Autodesk Fusion 360 part; units mm, degrees
(part 2 of 2)
extrude "Bottom cover snap 55" add sketch "Bottom cover snap 55 outline" along normal blind 5 bodies 21 in component "02 Snap-on front cover - PRINT"
ref_plane "WorkPlane21" through (52.5, 0, 0) normal (1, 0, 0) x (0, 1, 0) in component "02 Snap-on front cover - PRINT"
sketch "Top cover snap 55 outline" plane through (52.5, 0, 0) normal (1, 0, 0) x (0, 0, -1) in component "02 Snap-on front cover - PRINT"
  line L0 (-163.45, -14.2) -> (-164.25, -14.2)
  line L1 (-164.25, -14.2) -> (-164.25, -9)
  line L2 (-164.25, -9) -> (-165.2, -9)
  line L3 (-165.2, -9) -> (-165.2, -8.2)
  line L4 (-165.2, -8.2) -> (-164.25, -6.8)
  line L5 (-164.25, -6.8) -> (-163.45, -6.8)
  line L6 (-163.45, -6.8) -> (-163.45, -14.2)
extrude "Top cover snap 55" add sketch "Top cover snap 55 outline" along normal blind 5 bodies 21 in component "02 Snap-on front cover - PRINT"
ref_plane "WorkPlane22" through (156.5, 0, 0) normal (1, 0, 0) x (0, 1, 0) in component "02 Snap-on front cover - PRINT"
sketch "Bottom cover snap 159 outline" plane through (156.5, 0, 0) normal (1, 0, 0) x (0, 0, -1) in component "02 Snap-on front cover - PRINT"
  line L0 (-71.75, -14.2) -> (-72.95, -14.2)
  line L1 (-72.95, -14.2) -> (-72.95, -1.8)
  line L2 (-72.95, -1.8) -> (-71.75, -1.8)
  line L3 (-71.75, -1.8) -> (-70.8, -3.2)
  line L4 (-70.8, -3.2) -> (-70.8, -4)
  line L5 (-70.8, -4) -> (-71.75, -4)
  line L6 (-71.75, -4) -> (-71.75, -14.2)
extrude "Bottom cover snap 159" add sketch "Bottom cover snap 159 outline" along normal blind 5 bodies 21 in component "02 Snap-on front cover - PRINT"
ref_plane "WorkPlane23" through (156.5, 0, 0) normal (1, 0, 0) x (0, 1, 0) in component "02 Snap-on front cover - PRINT"
sketch "Top cover snap 159 outline" plane through (156.5, 0, 0) normal (1, 0, 0) x (0, 0, -1) in component "02 Snap-on front cover - PRINT"
  line L0 (-163.45, -14.2) -> (-164.25, -14.2)
  line L1 (-164.25, -14.2) -> (-164.25, -9)
  line L2 (-164.25, -9) -> (-165.2, -9)
  line L3 (-165.2, -9) -> (-165.2, -8.2)
  line L4 (-165.2, -8.2) -> (-164.25, -6.8)
  line L5 (-164.25, -6.8) -> (-163.45, -6.8)
  line L6 (-163.45, -6.8) -> (-163.45, -14.2)
extrude "Top cover snap 159" add sketch "Top cover snap 159 outline" along normal blind 5 bodies 21 in component "02 Snap-on front cover - PRINT"
ref_plane "WorkPlane24" through (0, 0, 72.3) normal (0, 0, 1) x (1, 0, 0) in component "02 Snap-on front cover - PRINT"
sketch "Ribbon roof attachment outline" plane through (0, 0, 72.3) normal (0, 0, 1) x (1, 0, 0) in component "02 Snap-on front cover - PRINT"
  line L0 (96, -16.2) -> (118, -16.2)
  line L1 (118, -16.2) -> (118, -12.6)
  line L2 (118, -12.6) -> (96, -12.6)
  line L3 (96, -12.6) -> (96, -16.2)
extrude "Ribbon roof attachment" add sketch "Ribbon roof attachment outline" along normal blind 2 bodies 21 in component "02 Snap-on front cover - PRINT"
ref_plane "WorkPlane25" through (0, 0, -4) normal (0, 0, 1) x (1, 0, 0) in component "02 Snap-on front cover - PRINT"
sketch "Continuous ribbon roof outline" plane through (0, 0, -4) normal (0, 0, 1) x (1, 0, 0) in component "02 Snap-on front cover - PRINT"
  line L0 (96, -13.8) -> (118, -13.8)
  line L1 (118, -13.8) -> (118, -12.6)
  line L2 (118, -12.6) -> (96, -12.6)
  line L3 (96, -12.6) -> (96, -13.8)
extrude "Continuous ribbon roof" add sketch "Continuous ribbon roof outline" along normal blind 78.3 bodies 21 in component "02 Snap-on front cover - PRINT"
ref_plane "WorkPlane26" through (0, 0, -4) normal (0, 0, 1) x (1, 0, 0) in component "02 Snap-on front cover - PRINT"
sketch "Ribbon roof side flange 96 outline" plane through (0, 0, -4) normal (0, 0, 1) x (1, 0, 0) in component "02 Snap-on front cover - PRINT"
  line L0 (96, -12.6) -> (98, -12.6)
  line L1 (98, -12.6) -> (98, -11.2)
  line L2 (98, -11.2) -> (96, -11.2)
  line L3 (96, -11.2) -> (96, -12.6)
extrude "Ribbon roof side flange 96" add sketch "Ribbon roof side flange 96 outline" along normal blind 76.3 bodies 21 in component "02 Snap-on front cover - PRINT"
ref_plane "WorkPlane27" through (0, 0, -4) normal (0, 0, 1) x (1, 0, 0) in component "02 Snap-on front cover - PRINT"
sketch "Ribbon roof side flange 116 outline" plane through (0, 0, -4) normal (0, 0, 1) x (1, 0, 0) in component "02 Snap-on front cover - PRINT"
  line L0 (116, -12.6) -> (118, -12.6)
  line L1 (118, -12.6) -> (118, -11.2)
  line L2 (118, -11.2) -> (116, -11.2)
  line L3 (116, -11.2) -> (116, -12.6)
extrude "Ribbon roof side flange 116" add sketch "Ribbon roof side flange 116 outline" along normal blind 76.3 bodies 21 in component "02 Snap-on front cover - PRINT"
ref_plane "WorkPlane28" through (0, 0, 1) normal (0, 0, 1) x (1, 0, 0) in component "02 Snap-on front cover - PRINT"
sketch "Lower ribbon cover catch bridge outline" plane through (0, 0, 1) normal (0, 0, 1) x (1, 0, 0) in component "02 Snap-on front cover - PRINT"
  line L0 (84.4, -13.8) -> (129.6, -13.8)
  line L1 (129.6, -13.8) -> (129.6, -12.6)
  line L2 (129.6, -12.6) -> (84.4, -12.6)
  line L3 (84.4, -12.6) -> (84.4, -13.8)
extrude "Lower ribbon cover catch bridge" add sketch "Lower ribbon cover catch bridge outline" along normal blind 6 bodies 21 in component "02 Snap-on front cover - PRINT"
ref_plane "WorkPlane29" through (0, 0, 1.5) normal (0, 0, 1) x (1, 0, 0) in component "02 Snap-on front cover - PRINT"
sketch "Left ribbon cover release catch outline" plane through (0, 0, 1.5) normal (0, 0, 1) x (1, 0, 0) in component "02 Snap-on front cover - PRINT"
  line L0 (84.4, -13.8) -> (85.6, -13.8)
  line L1 (85.6, -13.8) -> (85.6, -5.8)
  line L2 (85.6, -5.8) -> (86.6, -5.8)
  line L3 (86.6, -5.8) -> (86.6, -5.2)
  line L4 (86.6, -5.2) -> (85.6, -4.8)
  line L5 (85.6, -4.8) -> (84.4, -4.8)
  line L6 (84.4, -4.8) -> (84.4, -13.8)
extrude "Left ribbon cover release catch" add sketch "Left ribbon cover release catch outline" along normal blind 5 bodies 21 in component "02 Snap-on front cover - PRINT"
ref_plane "WorkPlane30" through (0, 0, 1.5) normal (0, 0, 1) x (1, 0, 0) in component "02 Snap-on front cover - PRINT"
sketch "Right ribbon cover release catch outline" plane through (0, 0, 1.5) normal (0, 0, 1) x (1, 0, 0) in component "02 Snap-on front cover - PRINT"
  line L0 (129.6, -13.8) -> (128.4, -13.8)
  line L1 (128.4, -13.8) -> (128.4, -5.8)
  line L2 (128.4, -5.8) -> (127.4, -5.8)
  line L3 (127.4, -5.8) -> (127.4, -5.2)
  line L4 (127.4, -5.2) -> (128.4, -4.8)
  line L5 (128.4, -4.8) -> (129.6, -4.8)
  line L6 (129.6, -4.8) -> (129.6, -13.8)
extrude "Right ribbon cover release catch" add sketch "Right ribbon cover release catch outline" along normal blind 5 bodies 21 in component "02 Snap-on front cover - PRINT"
ref_plane "WorkPlane1" through (0, 0, -29) normal (0, 0, 1) x (1, 0, 0) in component "03 Snap-on downward camera guard - PRINT"
sketch "Camera guard shell outline" plane through (0, 0, -29) normal (0, 0, 1) x (1, 0, 0) in component "03 Snap-on downward camera guard - PRINT"
  line L0 (85.2, -26.45) -> (128.8, -26.45)
  line L1 (130.8, -24.45) -> (130.8, 19.15)
  line L2 (128.8, 21.15) -> (85.2, 21.15)
  line L3 (83.2, 19.15) -> (83.2, -24.45)
  arc A0 (128.8, -26.45) -> (130.8, -24.45) centre (128.8, -24.45) ccw
  arc A1 (130.8, 19.15) -> (128.8, 21.15) centre (128.8, 19.15) ccw
  arc A2 (85.2, 21.15) -> (83.2, 19.15) centre (85.2, 19.15) ccw
  arc A3 (83.2, -24.45) -> (85.2, -26.45) centre (85.2, -24.45) ccw
extrude "Camera guard shell" add sketch "Camera guard shell outline" along normal blind 18.6 separate body makes body 22 in component "03 Snap-on downward camera guard - PRINT"
ref_plane "WorkPlane2" through (0, 0, -26.6) normal (0, 0, 1) x (1, 0, 0) in component "03 Snap-on downward camera guard - PRINT"
sketch "Camera cavity outline" plane through (0, 0, -26.6) normal (0, 0, 1) x (1, 0, 0) in component "03 Snap-on downward camera guard - PRINT"
  line L0 (85.6, -24.05) -> (128.4, -24.05)
  line L1 (128.4, -24.05) -> (128.4, 18.75)
  line L2 (128.4, 18.75) -> (85.6, 18.75)
  line L3 (85.6, 18.75) -> (85.6, -24.05)
extrude "Camera cavity" cut sketch "Camera cavity outline" along normal blind 16.3 bodies 22 in component "03 Snap-on downward camera guard - PRINT"
ref_plane "WorkPlane3" through (0, 0, -29.1) normal (0, 0, 1) x (1, 0, 0) in component "03 Snap-on downward camera guard - PRINT"
sketch "Fisheye aperture layout" plane through (0, 0, -29.1) normal (0, 0, 1) x (1, 0, 0) in component "03 Snap-on downward camera guard - PRINT"
  circle A0 centre (107, 0) radius 11
extrude "Fisheye aperture" cut sketch "Fisheye aperture layout" along normal blind 2.6 bodies 22 in component "03 Snap-on downward camera guard - PRINT"
ref_plane "WorkPlane4" through (0, 0, -19) normal (0, 0, 1) x (1, 0, 0) in component "03 Snap-on downward camera guard - PRINT"
sketch "Ribbon exit outline" plane through (0, 0, -19) normal (0, 0, 1) x (1, 0, 0) in component "03 Snap-on downward camera guard - PRINT"
  line L0 (98, -26.6) -> (116, -26.6)
  line L1 (116, -26.6) -> (116, -23.9)
  line L2 (116, -23.9) -> (98, -23.9)
  line L3 (98, -23.9) -> (98, -26.6)
extrude "Ribbon exit" cut sketch "Ribbon exit outline" along normal blind 8.7 bodies 22 in component "03 Snap-on downward camera guard - PRINT"
ref_plane "WorkPlane5" through (0, 0, -25) normal (0, 0, 1) x (1, 0, 0) in component "03 Snap-on downward camera guard - PRINT"
sketch "L flexible tongue clearance outline" plane through (0, 0, -25) normal (0, 0, 1) x (1, 0, 0) in component "03 Snap-on downward camera guard - PRINT"
  line L0 (83.1, -3.6) -> (85.7, -3.6)
  line L1 (85.7, -3.6) -> (85.7, 3.6)
  line L2 (85.7, 3.6) -> (83.1, 3.6)
  line L3 (83.1, 3.6) -> (83.1, -3.6)
extrude "L flexible tongue clearance" cut sketch "L flexible tongue clearance outline" along normal blind 14.7 bodies 22 in component "03 Snap-on downward camera guard - PRINT"
ref_plane "WorkPlane6" through (0, 0, -25) normal (0, 0, 1) x (1, 0, 0) in component "03 Snap-on downward camera guard - PRINT"
sketch "R flexible tongue clearance outline" plane through (0, 0, -25) normal (0, 0, 1) x (1, 0, 0) in component "03 Snap-on downward camera guard - PRINT"
  line L0 (128.3, -3.6) -> (130.9, -3.6)
  line L1 (130.9, -3.6) -> (130.9, 3.6)
  line L2 (130.9, 3.6) -> (128.3, 3.6)
  line L3 (128.3, 3.6) -> (128.3, -3.6)
extrude "R flexible tongue clearance" cut sketch "R flexible tongue clearance outline" along normal blind 14.7 bodies 22 in component "03 Snap-on downward camera guard - PRINT"
ref_plane "WorkPlane7" through (0, -3, 0) normal (0, 1, 0) x (0, 0, 1) in component "03 Snap-on downward camera guard - PRINT"
sketch "Left releasable camera snap outline" plane through (0, -3, 0) normal (0, 1, 0) x (1, 0, 0) in component "03 Snap-on downward camera guard - PRINT"
  line L0 (84.4, 25) -> (85.6, 25)
  line L1 (85.6, 25) -> (85.6, 8.5)
  line L2 (85.6, 8.5) -> (86.7, 8.5)
  line L3 (86.7, 8.5) -> (86.7, 7)
  line L4 (86.7, 7) -> (85.6, 5.4)
  line L5 (85.6, 5.4) -> (84.4, 5.4)
  line L6 (84.4, 5.4) -> (84.4, 25)
extrude "Left releasable camera snap" add sketch "Left releasable camera snap outline" along normal blind 6 bodies 22 in component "03 Snap-on downward camera guard - PRINT"
ref_plane "WorkPlane8" through (0, -3, 0) normal (0, 1, 0) x (0, 0, 1) in component "03 Snap-on downward camera guard - PRINT"
sketch "Right releasable camera snap outline" plane through (0, -3, 0) normal (0, 1, 0) x (1, 0, 0) in component "03 Snap-on downward camera guard - PRINT"
  line L0 (129.6, 25) -> (128.4, 25)
  line L1 (128.4, 25) -> (128.4, 8.5)
  line L2 (128.4, 8.5) -> (127.3, 8.5)
  line L3 (127.3, 8.5) -> (127.3, 7)
  line L4 (127.3, 7) -> (128.4, 5.4)
  line L5 (128.4, 5.4) -> (129.6, 5.4)
  line L6 (129.6, 5.4) -> (129.6, 25)
extrude "Right releasable camera snap" add sketch "Right releasable camera snap outline" along normal blind 6 bodies 22 in component "03 Snap-on downward camera guard - PRINT"
ref_plane "WorkPlane1" through (99, 0, 0) normal (1, 0, 0) x (0, 1, 0) in component "REFERENCE - nominal ribbon clearance 16 x 0.35 mm"
sketch "Nominal ribbon route outline" plane through (99, 0, 0) normal (1, 0, 0) x (0, 0, -1) in component "REFERENCE - nominal ribbon clearance 16 x 0.35 mm"
  line L0 (13, -17.675) -> (8.9063, -17.675)
  line L1 (8.9063, -17.675) -> (6.825, -14.553)
  line L2 (6.825, -14.553) -> (6.825, -13.0967)
  line L3 (6.825, -13.0967) -> (3.4496, -10.975)
  line L4 (3.4496, -10.975) -> (-73, -10.975)
  line L5 (-73, -10.975) -> (-73, -10.625)
  line L6 (-73, -10.625) -> (3.5504, -10.625)
  line L7 (3.5504, -10.625) -> (7.175, -12.9033)
  line L8 (7.175, -12.9033) -> (7.175, -14.447)
  line L9 (7.175, -14.447) -> (9.0937, -17.325)
  line L10 (9.0937, -17.325) -> (13, -17.325)
  line L11 (13, -17.325) -> (13, -17.675)
extrude "Nominal ribbon route" add sketch "Nominal ribbon route outline" along normal blind 16 separate body makes body 23 in component "REFERENCE - nominal ribbon clearance 16 x 0.35 mm"
ref_plane "WorkPlane31" through (0, -16.2, 0) normal (0, 1, 0) x (0, 0, 1) in component "02 Snap-on front cover - PRINT"
sketch "Purdue Hackers official flat logo recess 1 outline" plane through (0, -16.2, 0) normal (0, 1, 0) x (1, 0, 0) in component "02 Snap-on front cover - PRINT"
  line L0 (101.6666, -76) -> (91, -76)
  line L1 (91, -76) -> (91, -86.2945)
  line L2 (91, -86.2945) -> (101.6666, -86.2945)
  line L3 (101.6666, -86.2945) -> (101.6666, -76)
  line L4 (101.6666, -76) -> (101.6666, -76)
extrude "Purdue Hackers official flat logo recess 1" cut sketch "Purdue Hackers official flat logo recess 1 outline" along normal blind 0.6 bodies 21 in component "02 Snap-on front cover - PRINT"
ref_plane "WorkPlane32" through (0, -16.2, 0) normal (0, 1, 0) x (0, 0, 1) in component "02 Snap-on front cover - PRINT"
sketch "Purdue Hackers official flat logo recess 2 outline" plane through (0, -16.2, 0) normal (0, 1, 0) x (1, 0, 0) in component "02 Snap-on front cover - PRINT"
  line L0 (112.3334, -96.5892) -> (123, -96.5892)
  line L1 (123, -96.5892) -> (123, -76)
  line L2 (123, -76) -> (112.3334, -76)
  line L3 (112.3334, -76) -> (112.3334, -86.2945)
  line L4 (112.3334, -86.2945) -> (101.6666, -86.2945)
  line L5 (101.6666, -86.2945) -> (101.6666, -106.8837)
  line L6 (101.6666, -106.8837) -> (112.3334, -106.8837)
  line L7 (112.3334, -106.8837) -> (112.3334, -96.5892)
  line L8 (112.3334, -96.5892) -> (112.3334, -96.5892)
extrude "Purdue Hackers official flat logo recess 2" cut sketch "Purdue Hackers official flat logo recess 2 outline" along normal blind 0.6 bodies 21 in component "02 Snap-on front cover - PRINT"
ref_plane "WorkPlane33" through (0, -16.2, 0) normal (0, 1, 0) x (0, 0, 1) in component "02 Snap-on front cover - PRINT"
sketch "Logo corner separation for manifold print outline" plane through (0, -16.2, 0) normal (0, 1, 0) x (1, 0, 0) in component "02 Snap-on front cover - PRINT"
  line L0 (101.6666, -86.2945) -> (101.2666, -86.2945)
  line L1 (101.2666, -86.2945) -> (101.6666, -85.8945)
  line L2 (101.6666, -85.8945) -> (101.6666, -86.2945)
extrude "Logo corner separation for manifold print" add sketch "Logo corner separation for manifold print outline" along normal blind 0.6 bodies 21 in component "02 Snap-on front cover - PRINT"
ref_plane "WorkPlane36" through (0, 0, -9) normal (0, 0, 1) x (1, 0, 0) in component "01 Integral case mount and camera holder - PRINT"
sketch "7 mm retaining hook thickness 25 outline" plane through (0, 0, -9) normal (0, 0, 1) x (1, 0, 0) in component "01 Integral case mount and camera holder - PRINT"
  line L0 (12, -11) -> (38, -11)
  line L1 (38, -11) -> (38, 45)
  line L2 (38, 45) -> (12, 45)
  line L3 (12, 45) -> (12, -11)
extrude "7 mm retaining hook thickness 25" add sketch "7 mm retaining hook thickness 25 outline" along normal blind 2 bodies 20 in component "01 Integral case mount and camera holder - PRINT"
ref_plane "WorkPlane37" through (0, 0, -9) normal (0, 0, 1) x (1, 0, 0) in component "01 Integral case mount and camera holder - PRINT"
sketch "7 mm retaining hook thickness 189 outline" plane through (0, 0, -9) normal (0, 0, 1) x (1, 0, 0) in component "01 Integral case mount and camera holder - PRINT"
  line L0 (176, -11) -> (202, -11)
  line L1 (202, -11) -> (202, 45)
  line L2 (202, 45) -> (176, 45)
  line L3 (176, 45) -> (176, -11)
extrude "7 mm retaining hook thickness 189" add sketch "7 mm retaining hook thickness 189 outline" along normal blind 2 bodies 20 in component "01 Integral case mount and camera holder - PRINT"
fillet "Rounded retaining arm upper roots" radius 1.5 4 edges at (189, -11, 65) (25, -11, 65) (189, -6, 65) (25, -6, 65) on bodies 20 in component "01 Integral case mount and camera holder - PRINT"
fillet "Rounded retaining arm inner knees" radius 1.5 4 edges at (25, -6, 7) (189, -6, 7) (189, -1, -2) (25, -1, -2) on bodies 20 in component "01 Integral case mount and camera holder - PRINT"
fillet "Rounded retaining arm outside heels" radius 2 2 edges at (25, -11, -9) (189, -11, -9) on bodies 20 in component "01 Integral case mount and camera holder - PRINT"
fillet "Lower service cover clip root relief" radius 0.6 4 edges at (159, -14.2, 71.75) (55, -14.2, 71.75) (159, -14.2, 72.95) (55, -14.2, 72.95) on bodies 21 in component "02 Snap-on front cover - PRINT"
fillet "Upper service cover clip root relief" radius 0.4 4 edges at (159, -14.2, 163.45) (55, -14.2, 163.45) (159, -14.2, 164.25) (55, -14.2, 164.25) on bodies 21 in component "02 Snap-on front cover - PRINT"
ref_plane "WorkPlane38" through (0, 15.6, 0) normal (0, 1, 0) x (0, 0, 1) in component "01 Integral case mount and camera holder - PRINT"
sketch "Pi screw entry relief - 0.2 mm deep layout" plane through (0, 15.6, 0) normal (0, 1, 0) x (1, 0, 0) in component "01 Integral case mount and camera holder - PRINT"
  circle A0 centre (149.5, -78.5) radius 1.4
  circle A1 centre (198.5, -78.5) radius 1.4
  circle A2 centre (149.5, -136.5) radius 1.4
  circle A3 centre (198.5, -136.5) radius 1.4
extrude "Pi screw entry relief - 0.2 mm deep" cut sketch "Pi screw entry relief - 0.2 mm deep layout" along normal blind 0.2 bodies 20 in component "01 Integral case mount and camera holder - PRINT"
ref_plane "WorkPlane39" through (0, 0, -13.5) normal (0, 0, 1) x (1, 0, 0) in component "01 Integral case mount and camera holder - PRINT"
sketch "Camera screw entry relief - 0.2 mm deep layout" plane through (0, 0, -13.5) normal (0, 0, 1) x (1, 0, 0) in component "01 Integral case mount and camera holder - PRINT"
  circle A0 centre (117.5, -7.15) radius 1.1
  circle A1 centre (117.5, 6.35) radius 1.1
  circle A2 centre (96.5, -7.15) radius 1.1
  circle A3 centre (96.5, 6.35) radius 1.1
extrude "Camera screw entry relief - 0.2 mm deep" cut sketch "Camera screw entry relief - 0.2 mm deep layout" along normal blind 0.2 bodies 20 in component "01 Integral case mount and camera holder - PRINT"
sketch "Screw-fit coupon base outline" plane through (0, 0, 0) normal (0, 0, 1) x (1, 0, 0) in component "08 Screw-fit test coupon - TEST PRINT"
  line L0 (245, 0) -> (297, 0)
  line L1 (297, 0) -> (297, 44)
  line L2 (297, 44) -> (245, 44)
  line L3 (245, 44) -> (245, 0)
extrude "Screw-fit coupon base" add sketch "Screw-fit coupon base outline" along normal blind 2 separate body makes body 24 in component "08 Screw-fit test coupon - TEST PRINT"
ref_plane "WorkPlane1" through (0, 0, 2) normal (0, 0, 1) x (1, 0, 0) in component "08 Screw-fit test coupon - TEST PRINT"
sketch "Coupon label M2" plane through (0, 0, 2) normal (0, 0, 1) x (1, 0, 0) in component "08 Screw-fit test coupon - TEST PRINT"
  line L0 (246, 0.2) -> (246.5, 0.2)
  line L1 (246.5, 0.2) -> (246.5, 5.2)
  line L2 (246.5, 5.2) -> (246, 5.2)
  line L3 (246, 5.2) -> (246, 0.2)
  line L4 (249.5, 0.2) -> (250, 0.2)
  line L5 (250, 0.2) -> (250, 5.2)
  line L6 (250, 5.2) -> (249.5, 5.2)
  line L7 (249.5, 5.2) -> (249.5, 0.2)
  line L8 (246.65, 5.2) -> (247.9, 3.4)
  line L9 (247.9, 3.4) -> (247.55, 2.9)
  line L10 (247.55, 2.9) -> (246.65, 4.2)
  line L11 (246.65, 4.2) -> (246.65, 5.2)
  line L12 (249.35, 5.2) -> (248.1, 3.4)
  line L13 (248.1, 3.4) -> (248.45, 2.9)
  line L14 (248.45, 2.9) -> (249.35, 4.2)
  line L15 (249.35, 4.2) -> (249.35, 5.2)
  line L16 (251.65, 4.7) -> (253.35, 4.7)
  line L17 (253.35, 4.7) -> (253.35, 5.2)
  line L18 (253.35, 5.2) -> (251.65, 5.2)
  line L19 (251.65, 5.2) -> (251.65, 4.7)
  line L20 (253.5, 3.1) -> (254, 3.1)
  line L21 (254, 3.1) -> (254, 4.55)
  line L22 (254, 4.55) -> (253.5, 4.55)
  line L23 (253.5, 4.55) -> (253.5, 3.1)
  line L24 (251.65, 0.2) -> (253.35, 0.2)
  line L25 (253.35, 0.2) -> (253.35, 0.7)
  line L26 (253.35, 0.7) -> (251.65, 0.7)
  line L27 (251.65, 0.7) -> (251.65, 0.2)
  line L28 (251, 0.85) -> (251.5, 0.85)
  line L29 (251.5, 0.85) -> (251.5, 2.3)
  line L30 (251.5, 2.3) -> (251, 2.3)
  line L31 (251, 2.3) -> (251, 0.85)
  line L32 (251.65, 2.45) -> (253.35, 2.45)
  line L33 (253.35, 2.45) -> (253.35, 2.95)
  line L34 (253.35, 2.95) -> (251.65, 2.95)
  line L35 (251.65, 2.95) -> (251.65, 2.45)
extrude "Raised coupon label M2" add sketch "Coupon label M2" along normal blind 0.4 bodies 24 in component "08 Screw-fit test coupon - TEST PRINT"
ref_plane "WorkPlane2" through (0, 0, 2) normal (0, 0, 1) x (1, 0, 0) in component "08 Screw-fit test coupon - TEST PRINT"
sketch "M2 pilot 1.6 boss layout" plane through (0, 0, 2) normal (0, 0, 1) x (1, 0, 0) in component "08 Screw-fit test coupon - TEST PRINT"
  circle A0 centre (253, 9) radius 3.2
extrude "M2 pilot 1.6 boss" add sketch "M2 pilot 1.6 boss layout" along normal blind 7 bodies 24 in component "08 Screw-fit test coupon - TEST PRINT"
ref_plane "WorkPlane3" through (0, 0, 9) normal (0, 0, 1) x (1, 0, 0) in component "08 Screw-fit test coupon - TEST PRINT"
sketch "M2 pilot 1.6 bore layout" plane through (0, 0, 9) normal (0, 0, 1) x (1, 0, 0) in component "08 Screw-fit test coupon - TEST PRINT"
  circle A0 centre (253, 9) radius 0.8
extrude "M2 pilot 1.6 bore" cut sketch "M2 pilot 1.6 bore layout" against normal blind 5.2 bodies 24 in component "08 Screw-fit test coupon - TEST PRINT"
ref_plane "WorkPlane4" through (0, 0, 9) normal (0, 0, 1) x (1, 0, 0) in component "08 Screw-fit test coupon - TEST PRINT"
sketch "M2 pilot 1.6 board clearance layout" plane through (0, 0, 9) normal (0, 0, 1) x (1, 0, 0) in component "08 Screw-fit test coupon - TEST PRINT"
  circle A0 centre (253, 9) radius 1.1
extrude "M2 pilot 1.6 board clearance" cut sketch "M2 pilot 1.6 board clearance layout" against normal blind 1.4 bodies 24 in component "08 Screw-fit test coupon - TEST PRINT"
ref_plane "WorkPlane5" through (0, 0, 2) normal (0, 0, 1) x (1, 0, 0) in component "08 Screw-fit test coupon - TEST PRINT"
sketch "Coupon label 1.6" plane through (0, 0, 2) normal (0, 0, 1) x (1, 0, 0) in component "08 Screw-fit test coupon - TEST PRINT"
  line L0 (250.5, 16.9) -> (251, 16.9)
  line L1 (251, 16.9) -> (251, 18.35)
  line L2 (251, 18.35) -> (250.5, 18.35)
  line L3 (250.5, 18.35) -> (250.5, 16.9)
  line L4 (250.5, 14.65) -> (251, 14.65)
  line L5 (251, 14.65) -> (251, 16.1)
  line L6 (251, 16.1) -> (250.5, 16.1)
  line L7 (250.5, 16.1) -> (250.5, 14.65)
  circle A0 centre (252.3, 14.3) radius 0.3
  line L8 (254.05, 18.5) -> (255.75, 18.5)
  line L9 (255.75, 18.5) -> (255.75, 19)
  line L10 (255.75, 19) -> (254.05, 19)
  line L11 (254.05, 19) -> (254.05, 18.5)
  line L12 (255.9, 14.65) -> (256.4, 14.65)
  line L13 (256.4, 14.65) -> (256.4, 16.1)
  line L14 (256.4, 16.1) -> (255.9, 16.1)
  line L15 (255.9, 16.1) -> (255.9, 14.65)
  line L16 (254.05, 14) -> (255.75, 14)
  line L17 (255.75, 14) -> (255.75, 14.5)
  line L18 (255.75, 14.5) -> (254.05, 14.5)
  line L19 (254.05, 14.5) -> (254.05, 14)
  line L20 (253.4, 14.65) -> (253.9, 14.65)
  line L21 (253.9, 14.65) -> (253.9, 16.1)
  line L22 (253.9, 16.1) -> (253.4, 16.1)
  line L23 (253.4, 16.1) -> (253.4, 14.65)
  line L24 (253.4, 16.9) -> (253.9, 16.9)
  line L25 (253.9, 16.9) -> (253.9, 18.35)
  line L26 (253.9, 18.35) -> (253.4, 18.35)
  line L27 (253.4, 18.35) -> (253.4, 16.9)
  line L28 (254.05, 16.25) -> (255.75, 16.25)
  line L29 (255.75, 16.25) -> (255.75, 16.75)
  line L30 (255.75, 16.75) -> (254.05, 16.75)
  line L31 (254.05, 16.75) -> (254.05, 16.25)
extrude "Raised coupon label 1.6" add sketch "Coupon label 1.6" along normal blind 0.4 bodies 24 in component "08 Screw-fit test coupon - TEST PRINT"
ref_plane "WorkPlane6" through (0, 0, 2) normal (0, 0, 1) x (1, 0, 0) in component "08 Screw-fit test coupon - TEST PRINT"
sketch "M2 pilot 1.7 boss layout" plane through (0, 0, 2) normal (0, 0, 1) x (1, 0, 0) in component "08 Screw-fit test coupon - TEST PRINT"
  circle A0 centre (271, 9) radius 3.2
extrude "M2 pilot 1.7 boss" add sketch "M2 pilot 1.7 boss layout" along normal blind 7 bodies 24 in component "08 Screw-fit test coupon - TEST PRINT"
ref_plane "WorkPlane7" through (0, 0, 9) normal (0, 0, 1) x (1, 0, 0) in component "08 Screw-fit test coupon - TEST PRINT"
sketch "M2 pilot 1.7 bore layout" plane through (0, 0, 9) normal (0, 0, 1) x (1, 0, 0) in component "08 Screw-fit test coupon - TEST PRINT"
  circle A0 centre (271, 9) radius 0.85
extrude "M2 pilot 1.7 bore" cut sketch "M2 pilot 1.7 bore layout" against normal blind 5.2 bodies 24 in component "08 Screw-fit test coupon - TEST PRINT"
ref_plane "WorkPlane8" through (0, 0, 9) normal (0, 0, 1) x (1, 0, 0) in component "08 Screw-fit test coupon - TEST PRINT"
sketch "M2 pilot 1.7 board clearance layout" plane through (0, 0, 9) normal (0, 0, 1) x (1, 0, 0) in component "08 Screw-fit test coupon - TEST PRINT"
  circle A0 centre (271, 9) radius 1.1
extrude "M2 pilot 1.7 board clearance" cut sketch "M2 pilot 1.7 board clearance layout" against normal blind 1.4 bodies 24 in component "08 Screw-fit test coupon - TEST PRINT"
ref_plane "WorkPlane9" through (0, 0, 2) normal (0, 0, 1) x (1, 0, 0) in component "08 Screw-fit test coupon - TEST PRINT"
sketch "Coupon label 1.7" plane through (0, 0, 2) normal (0, 0, 1) x (1, 0, 0) in component "08 Screw-fit test coupon - TEST PRINT"
  line L0 (268.5, 16.9) -> (269, 16.9)
  line L1 (269, 16.9) -> (269, 18.35)
  line L2 (269, 18.35) -> (268.5, 18.35)
  line L3 (268.5, 18.35) -> (268.5, 16.9)
  line L4 (268.5, 14.65) -> (269, 14.65)
  line L5 (269, 14.65) -> (269, 16.1)
  line L6 (269, 16.1) -> (268.5, 16.1)
  line L7 (268.5, 16.1) -> (268.5, 14.65)
  circle A0 centre (270.3, 14.3) radius 0.3
  line L8 (272.05, 18.5) -> (273.75, 18.5)
  line L9 (273.75, 18.5) -> (273.75, 19)
  line L10 (273.75, 19) -> (272.05, 19)
  line L11 (272.05, 19) -> (272.05, 18.5)
  line L12 (273.9, 16.9) -> (274.4, 16.9)
  line L13 (274.4, 16.9) -> (274.4, 18.35)
  line L14 (274.4, 18.35) -> (273.9, 18.35)
  line L15 (273.9, 18.35) -> (273.9, 16.9)
  line L16 (273.9, 14.65) -> (274.4, 14.65)
  line L17 (274.4, 14.65) -> (274.4, 16.1)
  line L18 (274.4, 16.1) -> (273.9, 16.1)
  line L19 (273.9, 16.1) -> (273.9, 14.65)
extrude "Raised coupon label 1.7" add sketch "Coupon label 1.7" along normal blind 0.4 bodies 24 in component "08 Screw-fit test coupon - TEST PRINT"
ref_plane "WorkPlane10" through (0, 0, 2) normal (0, 0, 1) x (1, 0, 0) in component "08 Screw-fit test coupon - TEST PRINT"
sketch "M2 pilot 1.8 boss layout" plane through (0, 0, 2) normal (0, 0, 1) x (1, 0, 0) in component "08 Screw-fit test coupon - TEST PRINT"
  circle A0 centre (289, 9) radius 3.2
extrude "M2 pilot 1.8 boss" add sketch "M2 pilot 1.8 boss layout" along normal blind 7 bodies 24 in component "08 Screw-fit test coupon - TEST PRINT"
ref_plane "WorkPlane11" through (0, 0, 9) normal (0, 0, 1) x (1, 0, 0) in component "08 Screw-fit test coupon - TEST PRINT"
sketch "M2 pilot 1.8 bore layout" plane through (0, 0, 9) normal (0, 0, 1) x (1, 0, 0) in component "08 Screw-fit test coupon - TEST PRINT"
  circle A0 centre (289, 9) radius 0.9
extrude "M2 pilot 1.8 bore" cut sketch "M2 pilot 1.8 bore layout" against normal blind 5.2 bodies 24 in component "08 Screw-fit test coupon - TEST PRINT"
ref_plane "WorkPlane12" through (0, 0, 9) normal (0, 0, 1) x (1, 0, 0) in component "08 Screw-fit test coupon - TEST PRINT"
sketch "M2 pilot 1.8 board clearance layout" plane through (0, 0, 9) normal (0, 0, 1) x (1, 0, 0) in component "08 Screw-fit test coupon - TEST PRINT"
  circle A0 centre (289, 9) radius 1.1
extrude "M2 pilot 1.8 board clearance" cut sketch "M2 pilot 1.8 board clearance layout" against normal blind 1.4 bodies 24 in component "08 Screw-fit test coupon - TEST PRINT"
ref_plane "WorkPlane13" through (0, 0, 2) normal (0, 0, 1) x (1, 0, 0) in component "08 Screw-fit test coupon - TEST PRINT"
sketch "Coupon label 1.8" plane through (0, 0, 2) normal (0, 0, 1) x (1, 0, 0) in component "08 Screw-fit test coupon - TEST PRINT"
  line L0 (286.5, 16.9) -> (287, 16.9)
  line L1 (287, 16.9) -> (287, 18.35)
  line L2 (287, 18.35) -> (286.5, 18.35)
  line L3 (286.5, 18.35) -> (286.5, 16.9)
  line L4 (286.5, 14.65) -> (287, 14.65)
  line L5 (287, 14.65) -> (287, 16.1)
  line L6 (287, 16.1) -> (286.5, 16.1)
  line L7 (286.5, 16.1) -> (286.5, 14.65)
  circle A0 centre (288.3, 14.3) radius 0.3
  line L8 (290.05, 18.5) -> (291.75, 18.5)
  line L9 (291.75, 18.5) -> (291.75, 19)
  line L10 (291.75, 19) -> (290.05, 19)
  line L11 (290.05, 19) -> (290.05, 18.5)
  line L12 (291.9, 16.9) -> (292.4, 16.9)
  line L13 (292.4, 16.9) -> (292.4, 18.35)
  line L14 (292.4, 18.35) -> (291.9, 18.35)
  line L15 (291.9, 18.35) -> (291.9, 16.9)
  line L16 (291.9, 14.65) -> (292.4, 14.65)
  line L17 (292.4, 14.65) -> (292.4, 16.1)
  line L18 (292.4, 16.1) -> (291.9, 16.1)
  line L19 (291.9, 16.1) -> (291.9, 14.65)
  line L20 (290.05, 14) -> (291.75, 14)
  line L21 (291.75, 14) -> (291.75, 14.5)
  line L22 (291.75, 14.5) -> (290.05, 14.5)
  line L23 (290.05, 14.5) -> (290.05, 14)
  line L24 (289.4, 14.65) -> (289.9, 14.65)
  line L25 (289.9, 14.65) -> (289.9, 16.1)
  line L26 (289.9, 16.1) -> (289.4, 16.1)
  line L27 (289.4, 16.1) -> (289.4, 14.65)
  line L28 (289.4, 16.9) -> (289.9, 16.9)
  line L29 (289.9, 16.9) -> (289.9, 18.35)
  line L30 (289.9, 18.35) -> (289.4, 18.35)
  line L31 (289.4, 18.35) -> (289.4, 16.9)
  line L32 (290.05, 16.25) -> (291.75, 16.25)
  line L33 (291.75, 16.25) -> (291.75, 16.75)
  line L34 (291.75, 16.75) -> (290.05, 16.75)
  line L35 (290.05, 16.75) -> (290.05, 16.25)
extrude "Raised coupon label 1.8" add sketch "Coupon label 1.8" along normal blind 0.4 bodies 24 in component "08 Screw-fit test coupon - TEST PRINT"
ref_plane "WorkPlane14" through (0, 0, 2) normal (0, 0, 1) x (1, 0, 0) in component "08 Screw-fit test coupon - TEST PRINT"
sketch "Coupon label M2.5" plane through (0, 0, 2) normal (0, 0, 1) x (1, 0, 0) in component "08 Screw-fit test coupon - TEST PRINT"
  line L0 (246, 20.5) -> (246.5, 20.5)
  line L1 (246.5, 20.5) -> (246.5, 25.5)
  line L2 (246.5, 25.5) -> (246, 25.5)
  line L3 (246, 25.5) -> (246, 20.5)
  line L4 (249.5, 20.5) -> (250, 20.5)
  line L5 (250, 20.5) -> (250, 25.5)
  line L6 (250, 25.5) -> (249.5, 25.5)
  line L7 (249.5, 25.5) -> (249.5, 20.5)
  line L8 (246.65, 25.5) -> (247.9, 23.7)
  line L9 (247.9, 23.7) -> (247.55, 23.2)
  line L10 (247.55, 23.2) -> (246.65, 24.5)
  line L11 (246.65, 24.5) -> (246.65, 25.5)
  line L12 (249.35, 25.5) -> (248.1, 23.7)
  line L13 (248.1, 23.7) -> (248.45, 23.2)
  line L14 (248.45, 23.2) -> (249.35, 24.5)
  line L15 (249.35, 24.5) -> (249.35, 25.5)
  line L16 (251.65, 25) -> (253.35, 25)
  line L17 (253.35, 25) -> (253.35, 25.5)
  line L18 (253.35, 25.5) -> (251.65, 25.5)
  line L19 (251.65, 25.5) -> (251.65, 25)
  line L20 (253.5, 23.4) -> (254, 23.4)
  line L21 (254, 23.4) -> (254, 24.85)
  line L22 (254, 24.85) -> (253.5, 24.85)
  line L23 (253.5, 24.85) -> (253.5, 23.4)
  line L24 (251.65, 20.5) -> (253.35, 20.5)
  line L25 (253.35, 20.5) -> (253.35, 21)
  line L26 (253.35, 21) -> (251.65, 21)
  line L27 (251.65, 21) -> (251.65, 20.5)
  line L28 (251, 21.15) -> (251.5, 21.15)
  line L29 (251.5, 21.15) -> (251.5, 22.6)
  line L30 (251.5, 22.6) -> (251, 22.6)
  line L31 (251, 22.6) -> (251, 21.15)
  line L32 (251.65, 22.75) -> (253.35, 22.75)
  line L33 (253.35, 22.75) -> (253.35, 23.25)
  line L34 (253.35, 23.25) -> (251.65, 23.25)
  line L35 (251.65, 23.25) -> (251.65, 22.75)
  circle A0 centre (255.3, 20.8) radius 0.3
  line L36 (257.05, 25) -> (258.75, 25)
  line L37 (258.75, 25) -> (258.75, 25.5)
  line L38 (258.75, 25.5) -> (257.05, 25.5)
  line L39 (257.05, 25.5) -> (257.05, 25)
  line L40 (258.9, 21.15) -> (259.4, 21.15)
  line L41 (259.4, 21.15) -> (259.4, 22.6)
  line L42 (259.4, 22.6) -> (258.9, 22.6)
  line L43 (258.9, 22.6) -> (258.9, 21.15)
  line L44 (257.05, 20.5) -> (258.75, 20.5)
  line L45 (258.75, 20.5) -> (258.75, 21)
  line L46 (258.75, 21) -> (257.05, 21)
  line L47 (257.05, 21) -> (257.05, 20.5)
  line L48 (256.4, 23.4) -> (256.9, 23.4)
  line L49 (256.9, 23.4) -> (256.9, 24.85)
  line L50 (256.9, 24.85) -> (256.4, 24.85)
  line L51 (256.4, 24.85) -> (256.4, 23.4)
  line L52 (257.05, 22.75) -> (258.75, 22.75)
  line L53 (258.75, 22.75) -> (258.75, 23.25)
  line L54 (258.75, 23.25) -> (257.05, 23.25)
  line L55 (257.05, 23.25) -> (257.05, 22.75)
extrude "Raised coupon label M2.5" add sketch "Coupon label M2.5" along normal blind 0.4 bodies 24 in component "08 Screw-fit test coupon - TEST PRINT"
ref_plane "WorkPlane15" through (0, 0, 2) normal (0, 0, 1) x (1, 0, 0) in component "08 Screw-fit test coupon - TEST PRINT"
sketch "M2.5 pilot 2.0 boss layout" plane through (0, 0, 2) normal (0, 0, 1) x (1, 0, 0) in component "08 Screw-fit test coupon - TEST PRINT"
  circle A0 centre (253, 31) radius 4
extrude "M2.5 pilot 2.0 boss" add sketch "M2.5 pilot 2.0 boss layout" along normal blind 8 bodies 24 in component "08 Screw-fit test coupon - TEST PRINT"
ref_plane "WorkPlane16" through (0, 0, 10) normal (0, 0, 1) x (1, 0, 0) in component "08 Screw-fit test coupon - TEST PRINT"
sketch "M2.5 pilot 2.0 bore layout" plane through (0, 0, 10) normal (0, 0, 1) x (1, 0, 0) in component "08 Screw-fit test coupon - TEST PRINT"
  circle A0 centre (253, 31) radius 1
extrude "M2.5 pilot 2.0 bore" cut sketch "M2.5 pilot 2.0 bore layout" against normal blind 6.6 bodies 24 in component "08 Screw-fit test coupon - TEST PRINT"
ref_plane "WorkPlane17" through (0, 0, 10) normal (0, 0, 1) x (1, 0, 0) in component "08 Screw-fit test coupon - TEST PRINT"
sketch "M2.5 pilot 2.0 board clearance layout" plane through (0, 0, 10) normal (0, 0, 1) x (1, 0, 0) in component "08 Screw-fit test coupon - TEST PRINT"
  circle A0 centre (253, 31) radius 1.4
extrude "M2.5 pilot 2.0 board clearance" cut sketch "M2.5 pilot 2.0 board clearance layout" against normal blind 1.8 bodies 24 in component "08 Screw-fit test coupon - TEST PRINT"
ref_plane "WorkPlane18" through (0, 0, 2) normal (0, 0, 1) x (1, 0, 0) in component "08 Screw-fit test coupon - TEST PRINT"
sketch "Coupon label 2.0" plane through (0, 0, 2) normal (0, 0, 1) x (1, 0, 0) in component "08 Screw-fit test coupon - TEST PRINT"
  line L0 (248.65, 40.5) -> (250.35, 40.5)
  line L1 (250.35, 40.5) -> (250.35, 41)
  line L2 (250.35, 41) -> (248.65, 41)
  line L3 (248.65, 41) -> (248.65, 40.5)
  line L4 (250.5, 38.9) -> (251, 38.9)
  line L5 (251, 38.9) -> (251, 40.35)
  line L6 (251, 40.35) -> (250.5, 40.35)
  line L7 (250.5, 40.35) -> (250.5, 38.9)
  line L8 (248.65, 36) -> (250.35, 36)
  line L9 (250.35, 36) -> (250.35, 36.5)
  line L10 (250.35, 36.5) -> (248.65, 36.5)
  line L11 (248.65, 36.5) -> (248.65, 36)
  line L12 (248, 36.65) -> (248.5, 36.65)
  line L13 (248.5, 36.65) -> (248.5, 38.1)
  line L14 (248.5, 38.1) -> (248, 38.1)
  line L15 (248, 38.1) -> (248, 36.65)
  line L16 (248.65, 38.25) -> (250.35, 38.25)
  line L17 (250.35, 38.25) -> (250.35, 38.75)
  line L18 (250.35, 38.75) -> (248.65, 38.75)
  line L19 (248.65, 38.75) -> (248.65, 38.25)
  circle A0 centre (252.3, 36.3) radius 0.3
  line L20 (254.05, 40.5) -> (255.75, 40.5)
  line L21 (255.75, 40.5) -> (255.75, 41)
  line L22 (255.75, 41) -> (254.05, 41)
  line L23 (254.05, 41) -> (254.05, 40.5)
  line L24 (255.9, 38.9) -> (256.4, 38.9)
  line L25 (256.4, 38.9) -> (256.4, 40.35)
  line L26 (256.4, 40.35) -> (255.9, 40.35)
  line L27 (255.9, 40.35) -> (255.9, 38.9)
  line L28 (255.9, 36.65) -> (256.4, 36.65)
  line L29 (256.4, 36.65) -> (256.4, 38.1)
  line L30 (256.4, 38.1) -> (255.9, 38.1)
  line L31 (255.9, 38.1) -> (255.9, 36.65)
  line L32 (254.05, 36) -> (255.75, 36)
  line L33 (255.75, 36) -> (255.75, 36.5)
  line L34 (255.75, 36.5) -> (254.05, 36.5)
  line L35 (254.05, 36.5) -> (254.05, 36)
  line L36 (253.4, 36.65) -> (253.9, 36.65)
  line L37 (253.9, 36.65) -> (253.9, 38.1)
  line L38 (253.9, 38.1) -> (253.4, 38.1)
  line L39 (253.4, 38.1) -> (253.4, 36.65)
  line L40 (253.4, 38.9) -> (253.9, 38.9)
  line L41 (253.9, 38.9) -> (253.9, 40.35)
  line L42 (253.9, 40.35) -> (253.4, 40.35)
  line L43 (253.4, 40.35) -> (253.4, 38.9)
extrude "Raised coupon label 2.0" add sketch "Coupon label 2.0" along normal blind 0.4 bodies 24 in component "08 Screw-fit test coupon - TEST PRINT"
ref_plane "WorkPlane19" through (0, 0, 2) normal (0, 0, 1) x (1, 0, 0) in component "08 Screw-fit test coupon - TEST PRINT"
sketch "M2.5 pilot 2.1 boss layout" plane through (0, 0, 2) normal (0, 0, 1) x (1, 0, 0) in component "08 Screw-fit test coupon - TEST PRINT"
  circle A0 centre (271, 31) radius 4
extrude "M2.5 pilot 2.1 boss" add sketch "M2.5 pilot 2.1 boss layout" along normal blind 8 bodies 24 in component "08 Screw-fit test coupon - TEST PRINT"
ref_plane "WorkPlane20" through (0, 0, 10) normal (0, 0, 1) x (1, 0, 0) in component "08 Screw-fit test coupon - TEST PRINT"
sketch "M2.5 pilot 2.1 bore layout" plane through (0, 0, 10) normal (0, 0, 1) x (1, 0, 0) in component "08 Screw-fit test coupon - TEST PRINT"
  circle A0 centre (271, 31) radius 1.05
extrude "M2.5 pilot 2.1 bore" cut sketch "M2.5 pilot 2.1 bore layout" against normal blind 6.6 bodies 24 in component "08 Screw-fit test coupon - TEST PRINT"
ref_plane "WorkPlane21" through (0, 0, 10) normal (0, 0, 1) x (1, 0, 0) in component "08 Screw-fit test coupon - TEST PRINT"
sketch "M2.5 pilot 2.1 board clearance layout" plane through (0, 0, 10) normal (0, 0, 1) x (1, 0, 0) in component "08 Screw-fit test coupon - TEST PRINT"
  circle A0 centre (271, 31) radius 1.4
extrude "M2.5 pilot 2.1 board clearance" cut sketch "M2.5 pilot 2.1 board clearance layout" against normal blind 1.8 bodies 24 in component "08 Screw-fit test coupon - TEST PRINT"
ref_plane "WorkPlane22" through (0, 0, 2) normal (0, 0, 1) x (1, 0, 0) in component "08 Screw-fit test coupon - TEST PRINT"
sketch "Coupon label 2.1" plane through (0, 0, 2) normal (0, 0, 1) x (1, 0, 0) in component "08 Screw-fit test coupon - TEST PRINT"
  line L0 (266.65, 40.5) -> (268.35, 40.5)
  line L1 (268.35, 40.5) -> (268.35, 41)
  line L2 (268.35, 41) -> (266.65, 41)
  line L3 (266.65, 41) -> (266.65, 40.5)
  line L4 (268.5, 38.9) -> (269, 38.9)
  line L5 (269, 38.9) -> (269, 40.35)
  line L6 (269, 40.35) -> (268.5, 40.35)
  line L7 (268.5, 40.35) -> (268.5, 38.9)
  line L8 (266.65, 36) -> (268.35, 36)
  line L9 (268.35, 36) -> (268.35, 36.5)
  line L10 (268.35, 36.5) -> (266.65, 36.5)
  line L11 (266.65, 36.5) -> (266.65, 36)
  line L12 (266, 36.65) -> (266.5, 36.65)
  line L13 (266.5, 36.65) -> (266.5, 38.1)
  line L14 (266.5, 38.1) -> (266, 38.1)
  line L15 (266, 38.1) -> (266, 36.65)
  line L16 (266.65, 38.25) -> (268.35, 38.25)
  line L17 (268.35, 38.25) -> (268.35, 38.75)
  line L18 (268.35, 38.75) -> (266.65, 38.75)
  line L19 (266.65, 38.75) -> (266.65, 38.25)
  circle A0 centre (270.3, 36.3) radius 0.3
  line L20 (273.9, 38.9) -> (274.4, 38.9)
  line L21 (274.4, 38.9) -> (274.4, 40.35)
  line L22 (274.4, 40.35) -> (273.9, 40.35)
  line L23 (273.9, 40.35) -> (273.9, 38.9)
  line L24 (273.9, 36.65) -> (274.4, 36.65)
  line L25 (274.4, 36.65) -> (274.4, 38.1)
  line L26 (274.4, 38.1) -> (273.9, 38.1)
  line L27 (273.9, 38.1) -> (273.9, 36.65)
extrude "Raised coupon label 2.1" add sketch "Coupon label 2.1" along normal blind 0.4 bodies 24 in component "08 Screw-fit test coupon - TEST PRINT"
ref_plane "WorkPlane23" through (0, 0, 2) normal (0, 0, 1) x (1, 0, 0) in component "08 Screw-fit test coupon - TEST PRINT"
sketch "M2.5 pilot 2.2 boss layout" plane through (0, 0, 2) normal (0, 0, 1) x (1, 0, 0) in component "08 Screw-fit test coupon - TEST PRINT"
  circle A0 centre (289, 31) radius 4
extrude "M2.5 pilot 2.2 boss" add sketch "M2.5 pilot 2.2 boss layout" along normal blind 8 bodies 24 in component "08 Screw-fit test coupon - TEST PRINT"
ref_plane "WorkPlane24" through (0, 0, 10) normal (0, 0, 1) x (1, 0, 0) in component "08 Screw-fit test coupon - TEST PRINT"
sketch "M2.5 pilot 2.2 bore layout" plane through (0, 0, 10) normal (0, 0, 1) x (1, 0, 0) in component "08 Screw-fit test coupon - TEST PRINT"
  circle A0 centre (289, 31) radius 1.1
extrude "M2.5 pilot 2.2 bore" cut sketch "M2.5 pilot 2.2 bore layout" against normal blind 6.6 bodies 24 in component "08 Screw-fit test coupon - TEST PRINT"
ref_plane "WorkPlane25" through (0, 0, 10) normal (0, 0, 1) x (1, 0, 0) in component "08 Screw-fit test coupon - TEST PRINT"
sketch "M2.5 pilot 2.2 board clearance layout" plane through (0, 0, 10) normal (0, 0, 1) x (1, 0, 0) in component "08 Screw-fit test coupon - TEST PRINT"
  circle A0 centre (289, 31) radius 1.4
extrude "M2.5 pilot 2.2 board clearance" cut sketch "M2.5 pilot 2.2 board clearance layout" against normal blind 1.8 bodies 24 in component "08 Screw-fit test coupon - TEST PRINT"
ref_plane "WorkPlane26" through (0, 0, 2) normal (0, 0, 1) x (1, 0, 0) in component "08 Screw-fit test coupon - TEST PRINT"
sketch "Coupon label 2.2" plane through (0, 0, 2) normal (0, 0, 1) x (1, 0, 0) in component "08 Screw-fit test coupon - TEST PRINT"
  line L0 (284.65, 40.5) -> (286.35, 40.5)
  line L1 (286.35, 40.5) -> (286.35, 41)
  line L2 (286.35, 41) -> (284.65, 41)
  line L3 (284.65, 41) -> (284.65, 40.5)
  line L4 (286.5, 38.9) -> (287, 38.9)
  line L5 (287, 38.9) -> (287, 40.35)
  line L6 (287, 40.35) -> (286.5, 40.35)
  line L7 (286.5, 40.35) -> (286.5, 38.9)
  line L8 (284.65, 36) -> (286.35, 36)
  line L9 (286.35, 36) -> (286.35, 36.5)
  line L10 (286.35, 36.5) -> (284.65, 36.5)
  line L11 (284.65, 36.5) -> (284.65, 36)
  line L12 (284, 36.65) -> (284.5, 36.65)
  line L13 (284.5, 36.65) -> (284.5, 38.1)
  line L14 (284.5, 38.1) -> (284, 38.1)
  line L15 (284, 38.1) -> (284, 36.65)
  line L16 (284.65, 38.25) -> (286.35, 38.25)
  line L17 (286.35, 38.25) -> (286.35, 38.75)
  line L18 (286.35, 38.75) -> (284.65, 38.75)
  line L19 (284.65, 38.75) -> (284.65, 38.25)
  circle A0 centre (288.3, 36.3) radius 0.3
  line L20 (290.05, 40.5) -> (291.75, 40.5)
  line L21 (291.75, 40.5) -> (291.75, 41)
  line L22 (291.75, 41) -> (290.05, 41)
  line L23 (290.05, 41) -> (290.05, 40.5)
  line L24 (291.9, 38.9) -> (292.4, 38.9)
  line L25 (292.4, 38.9) -> (292.4, 40.35)
  line L26 (292.4, 40.35) -> (291.9, 40.35)
  line L27 (291.9, 40.35) -> (291.9, 38.9)
  line L28 (290.05, 36) -> (291.75, 36)
  line L29 (291.75, 36) -> (291.75, 36.5)
  line L30 (291.75, 36.5) -> (290.05, 36.5)
  line L31 (290.05, 36.5) -> (290.05, 36)
  line L32 (289.4, 36.65) -> (289.9, 36.65)
  line L33 (289.9, 36.65) -> (289.9, 38.1)
  line L34 (289.9, 38.1) -> (289.4, 38.1)
  line L35 (289.4, 38.1) -> (289.4, 36.65)
  line L36 (290.05, 38.25) -> (291.75, 38.25)
  line L37 (291.75, 38.25) -> (291.75, 38.75)
  line L38 (291.75, 38.75) -> (290.05, 38.75)
  line L39 (290.05, 38.75) -> (290.05, 38.25)
extrude "Raised coupon label 2.2" add sketch "Coupon label 2.2" along normal blind 0.4 bodies 24 in component "08 Screw-fit test coupon - TEST PRINT"
component "REFERENCE - INIU P51L-E2 115 x 73 x 29 mm" placed x (-1, 0, 0) y (0, 0, 1) z (0, 1, 0) at (129, -14, 68.5)
component "REFERENCE - Raspberry Pi4 rotated ports" placed x (0, 0, -1) y (1, 0, 0) z (0, -1, 0) at (131, 60, 166)
component "REFERENCE - Waveshare RPi Camera G PCB and lens" placed x (-1, 0, 0) y (0, 1, 0) z (0, 0, -1) at (126, -21.65, -8)
component "REFERENCE - six mount pads - compressed" placed x (1, 0, 0) y (0, 1, 0) z (0, 0, 1) at (0, 0, 0)
component "REFERENCE - upward-stepped frame - back wall assumed" placed x (1, 0, 0) y (0, 1, 0) z (0, 0, 1) at (0, 0, 0)
component "07 Upward-step fit gauge PRINT FIRST - PRINT" placed x (1, 0, 0) y (0, 1, 0) z (0, 0, 1) at (0, 0, 0)
component "01 Integral case mount and camera holder - PRINT" placed x (1, 0, 0) y (0, 1, 0) z (0, 0, 1) at (0, 0, 0)
component "02 Snap-on front cover - PRINT" placed x (1, 0, 0) y (0, 1, 0) z (0, 0, 1) at (0, 0, 0)
component "03 Snap-on downward camera guard - PRINT" placed x (1, 0, 0) y (0, 1, 0) z (0, 0, 1) at (0, 0, 0)
component "REFERENCE - nominal ribbon clearance 16 x 0.35 mm" placed x (1, 0, 0) y (0, 1, 0) z (0, 0, 1) at (0, 0, 0)
component "08 Screw-fit test coupon - TEST PRINT" placed x (1, 0, 0) y (0, 1, 0) z (0, 0, 1) at (0, 0, 0)
equation "wall = 2.4 mm" comment "Printed shell wall and tray thickness"
equation "battery_tray_height = 37 mm" comment "Battery chamber outside height"
equation "upper_height = 32 mm" comment "Pi chamber height above battery tray"
equation "lid_thickness = 2.4 mm" comment "Removable lid"
equation "pi_standoff_height = 5 mm" comment "Pi underside clearance"
equation "pad_recess_depth = 0.8 mm" comment "Use 3 mm rubber pads; 2.2 mm projects below case"
equation "camera_carrier_thickness = 3 mm" comment "Camera backplate"
equation "camera_standoff_height = 2.5 mm" comment "Clearance under camera PCB"
equation "camera_lens_opening = 22 mm" comment "Generous opening; check actual lens barrel before final print"
equation "camera_cap_height = 17 mm" comment "Cap height above carrier; lens must project beyond the front"
equation "snap_clearance = 0.35 mm" comment "Nominal printed locator clearance; fit-test before assembly"
equation "pi_screw_pilot = 2.1 mm" comment "Provisional PETG pilot. Fit-test with actual screws before the full print."
equation "d893 = pi_screw_pilot"
equation "d894 = pi_screw_pilot"
equation "d895 = pi_screw_pilot"
equation "d896 = pi_screw_pilot"
equation "camera_screw_pilot = 1.7 mm" comment "Provisional PETG pilot. Fit-test with actual screws before the full print."
equation "d898 = camera_screw_pilot"
equation "d899 = camera_screw_pilot"
equation "d900 = camera_screw_pilot"
equation "d901 = camera_screw_pilot"
named bodies: "INIU envelope - check supplied cable position", "Pi PCB 85 x 56 x 1.6", "USB3", "USB2", "Ethernet", "USB-C", "HDMI0", "HDMI1", "Audio", "Camera PCB 25 x 24", "left lower-ledge pad - 20 x 10 x 3", "left upper-ledge pad - 20 x 9 x 3", "left underside retaining pad - 16 x 14 x 3", "right lower-ledge pad - 20 x 10 x 3", "right upper-ledge pad - 20 x 9 x 3", "right underside retaining pad - 16 x 14 x 3", "Open-front case", "Front cover", "Camera guard shell", "Screw-fit coupon base"
